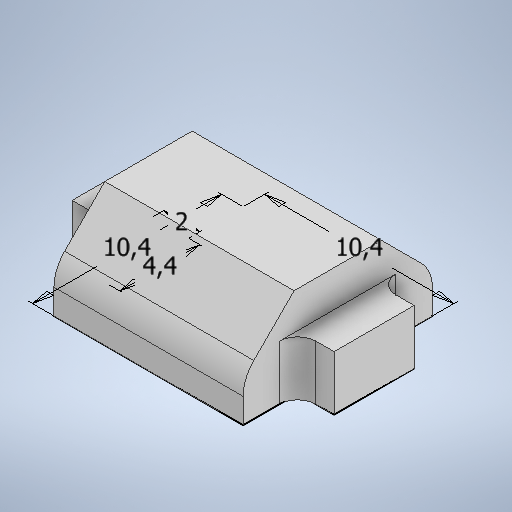
# Autodesk Inventor part: pinatel
Saved by Autodesk Inventor 2025 (Build 290162000, 162)
## iProperties
Created: 2026-10-30
Part Number: pinatel
Material: Типовые
Document SubType Name: Modeling
Designer: garin
Density: 1 g/cm^3
Appearance: По умолчанию
Author: garin
Autodesk Inventor part; units mm, degrees
ref_plane "YZ Plane" through (0, 0, 0) normal (1, 0, 0) x (0, 1, 0)
ref_plane "XZ Plane" through (0, 0, 0) normal (0, 1, 0) x (-1, 0, 0)
ref_plane "XY Plane" through (0, 0, 0) normal (0, 0, 1) x (1, 0, 0)
sketch "Эскиз1" plane through (0, 0, 0) normal (0, 1, 0) x (-1, 0, 0)
  line L0 (-5.2, 5.2) -> (5.2, 5.2)
  line L1 (5.2, 5.2) -> (5.2, -5.2)
  line L2 (5.2, -5.2) -> (-5.2, -5.2)
  line L3 (-5.2, -5.2) -> (-5.2, 5.2)
  line L4 (-5.2, 5.2) -> (5.2, -5.2) construction
  line L5 (5.2, 5.2) -> (-5.2, -5.2) construction
  line L6 (7.2, 2.2) -> (5.2, 2.2)
  line L7 (5.2, 2.2) -> (5.2, -2.2)
  line L8 (5.2, -2.2) -> (7.2, -2.2)
  line L9 (7.2, -2.2) -> (7.2, 2.2)
  line L10 (0, 5.2) -> (0, -5.2) construction
  line L11 (5.2, 0) -> (-5.2, 0) construction
  line L12 (-7.2, 2.2) -> (-5.2, 2.2)
  line L13 (-5.2, 2.2) -> (-5.2, -2.2)
  line L14 (-5.2, -2.2) -> (-7.2, -2.2)
  line L15 (-7.2, -2.2) -> (-7.2, 2.2)
  point P0 (0, 0)
  dimension "d0" = 10.4
  dimension "d1" = 10.4
  dimension "d2" = 2
  dimension "d3" = 4.4
  constraints: 32 end point, 7 midpoint, 4 parallel, 4 symmetric about line, 2 horizontal, 2 perpendicular
  measures "d0" distance of L1.end L2.end
  measures "d1" distance of L0.end L1.end
  measures "d2" distance of L8.end L7.end
  measures "d3" distance of L7.end L6.end
extrude "Выдавливание1" add sketch "Эскиз1" along normal blind 5 contours L0 L1 L2 L3
chamfer "Фаска1" distance 2.8 angle 45 2 edges at (0, 5, 5.2) (0, 5, -5.2)
fillet "Сопряжение2" radius 2 2 edges at (0, 2.2, -5.2) (0, 2.2, 5.2)
extrude "Выдавливание2" add sketch "Эскиз1" along normal blind 3 contours L3 L14 L15 L12 | L6 L9 L8 L1
fillet "Сопряжение3" radius 1 4 edges at (5.2, 1.5, -2.2) (5.2, 1.5, 2.2) (-5.2, 1.5, -2.2) (-5.2, 1.5, 2.2)
